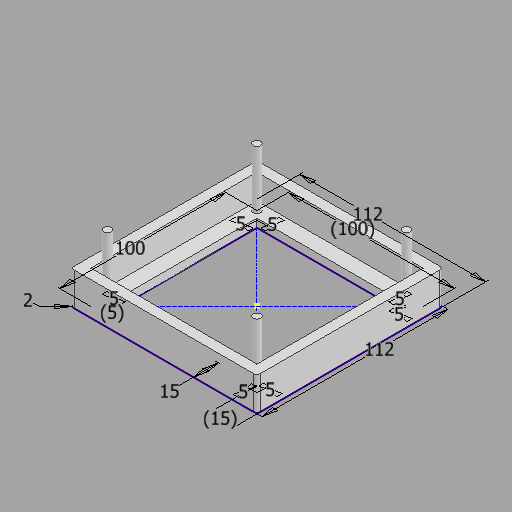
# Autodesk Inventor part: SEONSOR_Bottom
Saved by Autodesk Inventor 2027 (Build 310192000, 192)
## iProperties
Created: 2026-11-12
Part Number: SEONSOR_Bottom
Material: Generic
Document SubType Name: Modeling
Designer: jyjhm
Density: 1 g/cm^3
Appearance: Default
Author: jyjhm
Autodesk Inventor part; units mm, degrees
ref_plane "YZ Plane" through (0, 0, 0) normal (1, 0, 0) x (0, 1, 0)
ref_plane "XZ Plane" through (0, 0, 0) normal (0, 1, 0) x (-1, 0, 0)
ref_plane "XY Plane" through (0, 0, 0) normal (0, 0, 1) x (1, 0, 0)
sketch "Sketch1" plane through (0, 0, 0) normal (0, 1, 0) x (-1, 0, 0)
  line L0 (-54, -56) -> (54, -56)
  line L1 (56, -54) -> (56, 54)
  line L2 (54, 56) -> (-54, 56)
  line L3 (-56, 54) -> (-56, -54)
  line L4 (-56, -56) -> (56, 56) construction
  line L5 (56, -56) -> (-56, 56) construction
  line L6 (-50, -50) -> (50, -50)
  line L7 (50, -50) -> (50, 50)
  line L8 (50, 50) -> (-50, 50)
  line L9 (-50, 50) -> (-50, -50)
  line L10 (-50, -50) -> (50, 50) construction
  line L11 (50, -50) -> (-50, 50) construction
  arc A0 (56, 54) -> (54, 56) centre (54, 54) ccw
  arc A1 (-54, 56) -> (-56, 54) centre (-54, 54) ccw
  arc A2 (-56, -54) -> (-54, -56) centre (-54, -54) ccw
  arc A3 (54, -56) -> (56, -54) centre (54, -54) ccw
  line L12 (-41, -41) -> (41, -41)
  line L13 (41, -41) -> (41, 41)
  line L14 (41, 41) -> (-41, 41)
  line L15 (-41, 41) -> (-41, -41)
  line L16 (-41, -41) -> (41, 41) construction
  line L17 (41, -41) -> (-41, 41) construction
  circle A4 centre (45, 45) radius 2.2451
  circle A5 centre (-45, 45) radius 2.2451
  circle A6 centre (-45, -45) radius 2.2451
  circle A7 centre (45, -45) radius 2.2451
  point P0 (0, 0)
  dimension "d0" = 112
  dimension "d1" = 112
  dimension "d2" = 100
  dimension "d3" = 100
  dimension "d4" = 2
  dimension "d7" = 15
  dimension "d8" = 15
  dimension "d9" = 5
  dimension "d10" = 5
  dimension "d11" = 5
  dimension "d12" = 5
  dimension "d13" = 5
  dimension "d14" = 5
  dimension "d15" = 5
  dimension "d16" = 5
  constraints: 36 end point, 11 point on line, 8 centre point, 8 point on circle, 8 tangent, 6 midpoint, 6 parallel, 3 equal radius, 3 horizontal, 3 perpendicular
  measures "d0" distance of L5.end L4.start
  measures "d1" distance of L4.start L5.start
  measures "d2" distance of L6.end L7.end
  measures "d3" distance of L6.start L6.end
  measures "d4" radius of A0
  measures "d7" distance between parallel lines of L2 L14
  measures "d8" distance between parallel lines of L3 L15
  measures "d9" distance from line of L9 A5.centre
  measures "d10" distance from line of L8 A5.centre
  measures "d11" distance from line of L6 A6.centre
  measures "d12" distance from line of L9 A6.centre
  measures "d13" distance from line of L6 A7.centre
  measures "d14" distance from line of L7 A7.centre
  measures "d15" distance from line of L7 A4.centre
  measures "d16" distance from line of L8 A4.centre
extrude "Extrusion1" add sketch "Sketch1" along normal blind 5 contours L9 L8 L7 L6
extrude "Extrusion2" add sketch "Sketch1" along normal blind 20 contours A2 L3 A1 L2 A0 L1 A3 L0
extrude "Extrusion3" add sketch "Sketch1" along normal blind 40 contours A4 | A5 | A6 | A7
body "Solid1"
